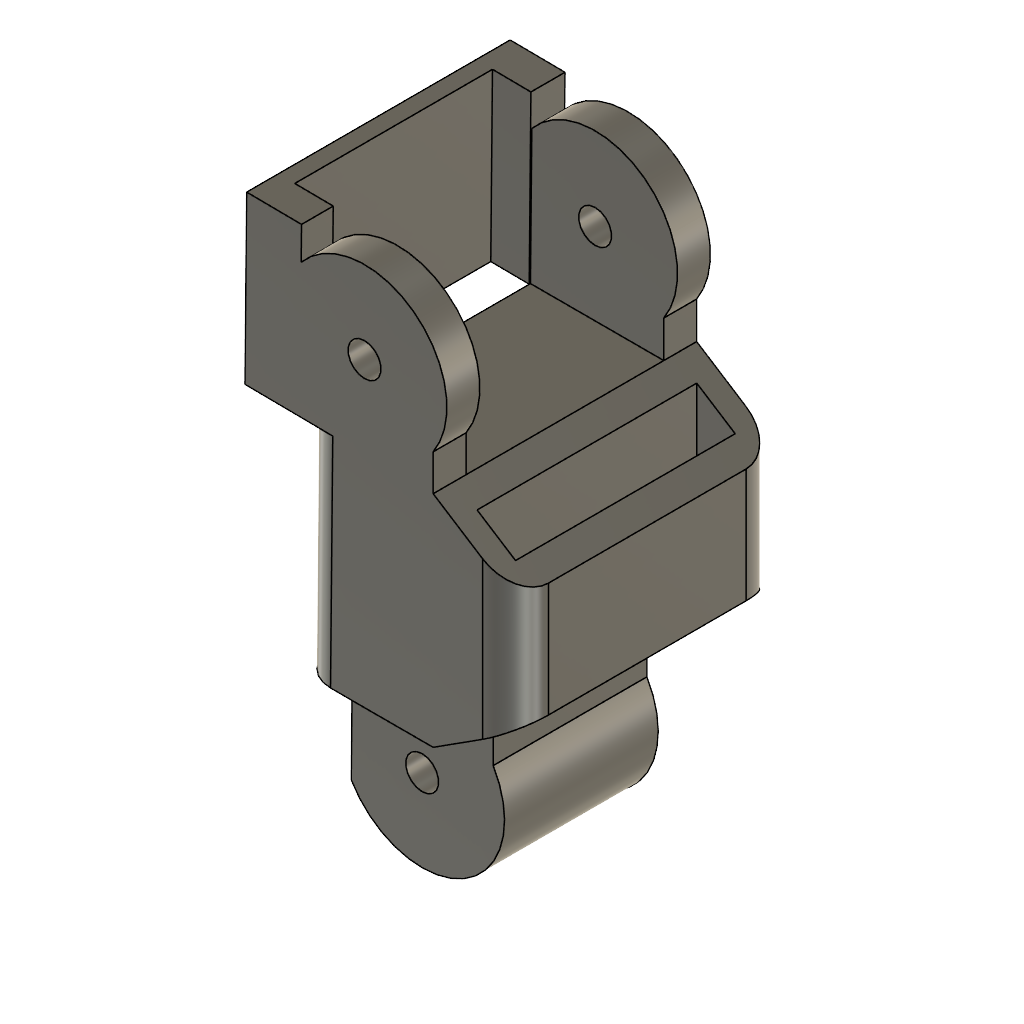
Fixed Hand Assembly V2 (Autodesk Fusion 360 archive; units mm, degrees)
design "Thumb END"
part number: 2026-11-07-22-03-41-443
Autodesk Fusion 360 part; units mm, degrees
sketch "Sketch1" plane through (0, 0, 0) normal (0, 1, 0) x (1, 0, 0)
  line L0 (0, 0) -> (25, 0)
  line L1 (25, 0) -> (25, -20)
  line L2 (25, -20) -> (0, -20)
  line L3 (0, -20) -> (0, 0)
  line L4 (12.5, -20) -> (25, -12)
  line L5 (12.5, 0) -> (25, -8)
  dimension "d1" = 25
  dimension "d2" = 20
  dimension "d3" = 8
  dimension "d4" = 8
  constraint horizontal L0
  constraint vertical L1
  constraint horizontal L2
  constraint vertical L3
  constraint coincident L0.start L3.end
  constraint midpoint L2 L4.start
  constraint coincident L1 L4.end
  constraint midpoint L0 L5.start
  constraint coincident L1 L5.end
  measures "d1" distance of L0.start L0.end
  measures "d2" distance of L0.start L2.end
  measures "d3" distance of L1.end L4.end
  measures "d4" distance of L0.end L5.end
extrude "Extrude1" add sketch "Sketch1" along normal mid plane 24 contours L0 L1 L2 L3 L4 L5 makes body 1
sketch "Sketch2" plane through (0, 0, 0) normal (0, 1, 0) x (1, 0, 0)
  circle A0 centre (6.5, -27.5) radius 7.5
  line L0 (0.0314, -20) -> (12.9686, -20)
  line L1 (12.9686, -20) -> (12.9686, -23.7043)
  line L2 (12.9686, -23.7043) -> (0.0314, -23.7043)
  line L3 (0.0314, -23.7043) -> (0.0314, -20)
  point P0 (12.5, -20)
  dimension "d7" = 15
  dimension "d8" = 7.5
  dimension "d9" = 6
  constraint horizontal L0
  constraint vertical L1
  constraint horizontal L2
  constraint vertical L3
  constraint coincident A0 L1.end
  constraint coincident A0 L2.end
  measures "d7" diameter of A0
  measures "d8" vertical distance of A0.centre P0
  measures "d9" horizontal distance of A0.centre P0
extrude "Extrude2" add sketch "Sketch2" along normal mid plane 14 bodies 1
sketch "Sketch3" plane through (0, -12, 0) normal (0, -1, 0) x (1, 0, 0)
  line L0 (25, 12) -> (12.5, 20)
  line L1 (12.5, 20) -> (0, 20)
  line L2 (0, 20) -> (0, 0)
  line L3 (0, 0) -> (12.5, 0)
  line L4 (12.5, 0) -> (25, 8)
  line L5 (25, 8) -> (25, 12)
  circle A0 centre (6.25, -7.5) radius 7.5
  line L6 (0, 0) -> (12.4995, 0)
  line L7 (12.4995, 0) -> (12.4995, -4.343)
  line L8 (12.4995, -4.343) -> (0, -4.343)
  line L9 (0, -4.343) -> (0, 0)
  dimension "d12" = 15
  dimension "d13" = 7.5
  dimension "d14" = 6.25
  constraint horizontal L6
  constraint vertical L7
  constraint horizontal L8
  constraint vertical L9
  constraint coincident L2.end L3.start
  measures "d12" diameter of A0
  measures "d13" vertical distance of L3.end A0.centre
  measures "d14" horizontal distance of L3.end A0.centre
extrude "Extrude3" add sketch "Sketch3" against normal blind 3 contours L3 A0 L6 L7 | L3 A0 L6 L9 | A0 L7 L8 L9 | A0 L7 L8 L9 bodies 1
sketch "Sketch4" plane through (0, 12, 0) normal (0, 1, 0) x (-1, 0, 0)
  line L0 (-12.5, 20) -> (-25, 12)
  line L1 (-25, 12) -> (-25, 8)
  line L2 (-25, 8) -> (-12.5, 0)
  line L3 (-12.5, 0) -> (0, 0)
  line L4 (0, 0) -> (0, 20)
  line L5 (0, 20) -> (-12.5, 20)
  circle A0 centre (-6.25, -7.45) radius 7.5
  line L6 (-12.5, 0) -> (-0.0053, 0)
  line L7 (-0.0053, 0) -> (-0.0053, -3.8158)
  line L8 (-0.0053, -3.8158) -> (-12.5, -3.8158)
  line L9 (-12.5, -3.8158) -> (-12.5, 0)
  dimension "d17" = 15
  dimension "d18" = 7.45
  dimension "d19" = 6.25
  constraint horizontal L6
  constraint vertical L7
  constraint horizontal L8
  constraint vertical L9
  constraint coincident L2.end L3.start
  measures "d17" diameter of A0
  measures "d18" vertical distance of L3.end A0.centre
  measures "d19" horizontal distance of L3.end A0.centre
extrude "Extrude4" add sketch "Sketch4" against normal blind 3 contours L3 A0 L6 L9 | L3 A0 L6 L7 | L3 A0 L6 L7 L8 L9 | A0 L7 L8 L9 bodies 1
hole "Hole1" at (6.5, 7, 27.5) direction (0, -1, 0) diameter 3 end through all bodies 1
hole "Hole2" at (6.25, 12, -7.45) direction (0, -1, 0) diameter 3 end through all bodies 1
move_body "Move1" bodies 1 to x (-1, 0, 0) y (0, 1, 0) z (0, 0, -1) at (-2.5, 0, 35)
move_body "Move2" bodies 1 to x (-1, 0, 0) y (0, -1, 0) z (0, 0, 1) at (-55, -24, 0)
sketch "Sketch5" plane through (0, -36, 0) normal (0, -1, 0) x (1, 0, 0)
  circle A0 centre (-46.25, 42.45) radius 1.5
  line L0 (-40, 15) -> (-27.5, 23)
  line L1 (-27.5, 23) -> (-27.5, 27)
  line L2 (-27.5, 27) -> (-40, 35)
  line L3 (-40, 35) -> (-40, 38.3042)
  arc A1 (-40, 38.3042) -> (-52.4947, 38.2962) centre (-46.25, 42.45) ccw
  line L4 (-52.4947, 38.2962) -> (-52.4947, 35)
  line L5 (-52.4947, 35) -> (-52.5, 35)
  line L6 (-52.5, 35) -> (-52.5, 15)
  line L7 (-52.5, 15) -> (-40, 15)
  line L8 (-52, 49) -> (-52.4947, 0.4697)
  line L9 (-52.4947, 0.4697) -> (-54.3255, 0.4883)
  line L10 (-54.3255, 0.4883) -> (-54.3255, 49)
  line L11 (-54.3255, 49) -> (-52, 49)
  constraint perpendicular L8 L9
  constraint vertical L10
  constraint horizontal L11
extrude "Extrude5" cut sketch "Sketch5" against normal blind 39 contours A1 L4 L5 L6 L7 L8 L9 L10 L11 | A1 L4 L5 L6 L7 L8 bodies 1
sketch "Sketch6" plane through (-52.494, 0, 0.5351) normal (-0.999948, 0, 0.010193) x (0, -1, 0)
  line L0 (31, 14.4657) -> (36, 14.4657)
  line L1 (36, 14.4657) -> (36, 46.7112)
  line L2 (36, 46.7112) -> (33, 46.7112)
  line L3 (33, 46.7112) -> (33, 34.4667)
  line L4 (33, 34.4667) -> (15, 34.4667)
  line L5 (15, 34.4667) -> (15, 46.7618)
  line L6 (15, 46.7618) -> (12, 46.7618)
  line L7 (12, 46.7618) -> (12, 14.4657)
  line L8 (12, 14.4657) -> (17, 14.4657)
  line L9 (17, 14.4657) -> (17, 3.1579)
  line L10 (17, 3.1579) -> (31, 3.1579)
  line L11 (31, 3.1579) -> (31, 14.4657)
  line L12 (12, 34.4667) -> (36, 34.4667)
  line L13 (36, 34.4667) -> (36, 46.7112)
  line L14 (36, 46.7112) -> (12, 46.7112)
  line L15 (12, 46.7112) -> (12, 34.4667)
  constraint horizontal L12
  constraint vertical L13
  constraint horizontal L14
  constraint vertical L15
  constraint coincident L1.end L2.start
  constraint coincident L7 L12.start
extrude "Extrude6" add sketch "Sketch6" along normal blind 5 separate body contours L1 L2 L3 L12 L13 L14 | L3 L4 L5 L12 L14 | L5 L7 L12 L14 L15 makes body 2
sketch "Sketch7" plane through (0.4761, 0, 46.7088) normal (0.010193, 0, 0.999948) x (0, 1, 0)
  line L0 (-36, 52.4967) -> (-12, 52.4967)
  line L1 (-12, 52.4967) -> (-12, 57.4967)
  line L2 (-12, 57.4967) -> (-36, 57.4967)
  line L3 (-36, 57.4967) -> (-36, 52.4967)
  line L4 (-15.1122, 52.4967) -> (-33.1122, 52.4967)
  line L5 (-33.1122, 52.4967) -> (-33.1122, 55.9967)
  line L6 (-33.1122, 55.9967) -> (-15.1122, 55.9967)
  line L7 (-15.1122, 55.9967) -> (-15.1122, 52.4967)
  dimension "d30" = 18
  dimension "d31" = 3.5
  constraint horizontal L4
  constraint vertical L5
  constraint horizontal L6
  constraint vertical L7
  constraint coincident L0 L4.start
  measures "d30" distance of L4.start L4.end
  measures "d31" distance of L4.start L6.end
extrude "Extrude7" cut sketch "Sketch7" against normal blind 16 contours L0 L4 L5 L6 L7 bodies 2
extrude "Extrude8" add 1 faces at (-54.8511, -13.0374, 47.2728) along direction (0.010193, 0, 0.999948) blind 3 on bodies 2 bodies 1 2
sketch "Sketch8" plane through (0, -36, 0) normal (0, -1, 0) x (1, 0, 0)
  line L0 (-52.1427, 35) -> (-52.3466, 15)
  line L1 (-52.3466, 15) -> (-40, 15)
  line L2 (-40, 15) -> (-27.5, 23)
  line L3 (-27.5, 23) -> (-27.5, 27)
  line L4 (-27.5, 27) -> (-40, 35)
  line L5 (-40, 35) -> (-40, 38.3042)
  arc A0 (-40, 38.3042) -> (-52.0179, 47.2439) centre (-46.25, 42.45) ccw
  line L6 (-52.0179, 47.2439) -> (-51.9873, 50.2437)
  line L7 (-51.9873, 50.2437) -> (-56.9871, 50.2947)
  line L8 (-56.9871, 50.2947) -> (-57.1424, 35.051)
  line L9 (-57.1424, 35.051) -> (-52.1427, 35)
  circle A1 centre (-46.25, 42.45) radius 1.5
  line L10 (-32.5, 30.2) -> (-27.5, 30.2)
  line L11 (-27.5, 30.2) -> (-27.5, 19.2)
  line L12 (-27.5, 19.2) -> (-32.5, 19.2)
  line L13 (-32.5, 19.2) -> (-32.5, 30.2)
  dimension "d36" = 5
  dimension "d37" = 11
  dimension "d38" = 5
  constraint horizontal L10
  constraint vertical L11
  constraint horizontal L12
  constraint vertical L13
  constraint coincident L4 L10.start
  measures "d36" distance of L10.start L10.end
  measures "d37" distance of L10.start L12.end
  measures "d38" distance of L3.end L13
extrude "Extrude9" cut sketch "Sketch8" against normal blind 29 contours L2 L3 L4 L11 L13 | L2 L11 L12 L13 | L4 L10 L11 bodies 1
sketch "Sketch9" plane through (0, 0, 35) normal (0, 0, 1) x (-1, 0, 0)
  line L0 (52.1427, 15) -> (52.1427, 15.1122)
  line L1 (52.1427, 15.1122) -> (52.1427, 33)
  line L2 (52.1427, 33) -> (40, 33)
  line L3 (40, 33) -> (40, 12)
  line L4 (40, 12) -> (40.0005, 12)
  line L5 (40.0005, 12) -> (40.0005, 15)
  line L6 (40.0005, 15) -> (52.1427, 15)
  line L7 (32.5, 12) -> (40, 12)
  line L8 (40, 12) -> (40, 36)
  line L9 (40, 36) -> (32.5, 36)
  line L10 (32.5, 36) -> (32.5, 12)
  line L11 (38, 14) -> (38, 34)
  line L12 (38, 34) -> (34.5, 34)
  line L13 (34.5, 34) -> (34.5, 14)
  line L14 (34.5, 14) -> (38, 14)
  dimension "d41" = -2
  constraint horizontal L7
  constraint vertical L8
  constraint horizontal L9
  constraint vertical L10
extrude "Extrude10" cut sketch "Sketch9" against normal blind 20.5 contours L11 L12 L13 L14 bodies 1
fillet "Fillet1" radius 3 4 edges at (-52.2446, -36, 25) (-32.5, -36, 25) (-32.5, -12, 25) (-52.2446, -12, 25) on bodies 1

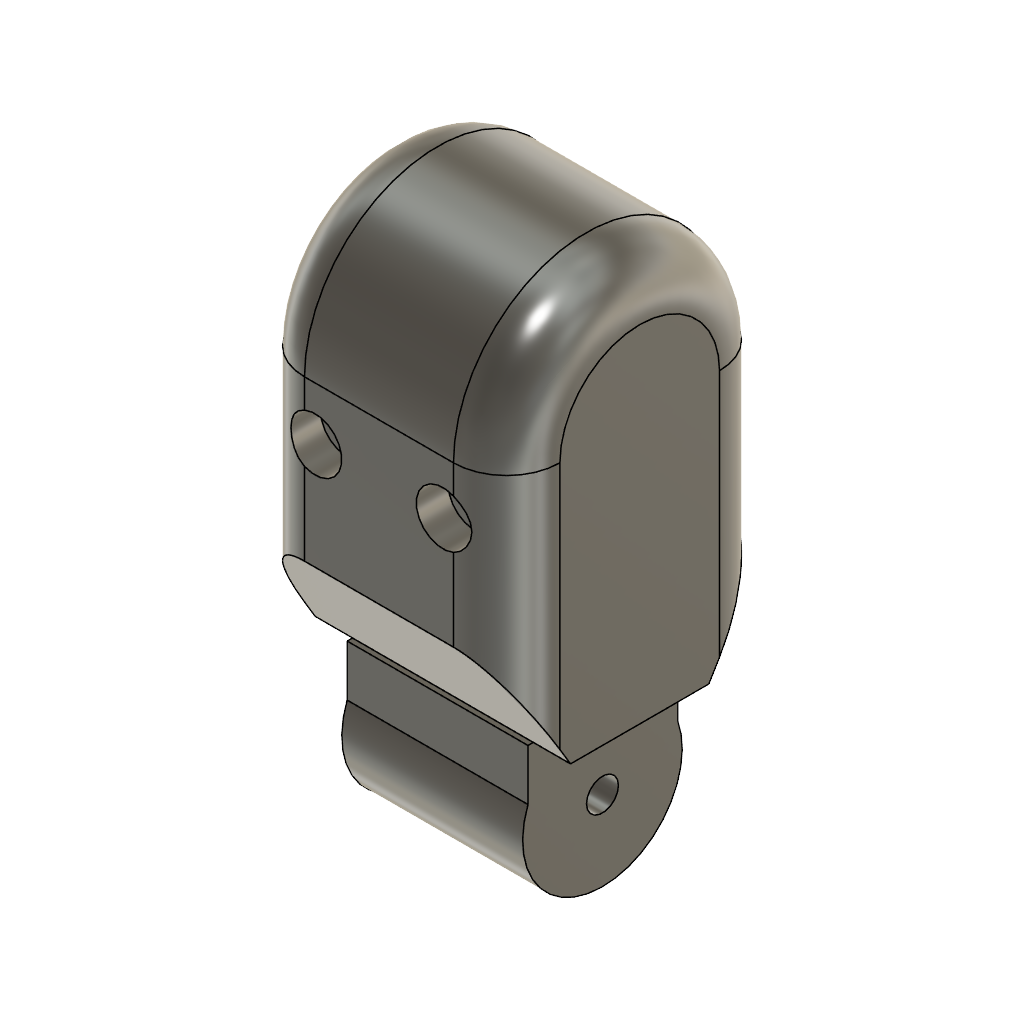
design "Thumb DISTAL"
part number: 2026-11-07-21-49-28-022
Autodesk Fusion 360 part; units mm, degrees
sketch "Sketch1" plane through (0, 0, 0) normal (1, 0, 0) x (0, 1, 0)
  line L0 (0, 0) -> (25, 0)
  line L1 (25, 0) -> (25, 25)
  line L2 (25, 25) -> (0, 25)
  line L3 (0, 25) -> (0, 0)
  circle A0 centre (12.5, 25) radius 12.5
  dimension "d1" = 25
  dimension "d2" = 25
  constraint horizontal L0
  constraint vertical L1
  constraint horizontal L2
  constraint vertical L3
  constraint coincident L0.start L3.end
  constraint midpoint L2 A0.centre
  constraint coincident L1.end A0
  measures "d1" distance of L0.start L0.end
  measures "d2" distance of L0.start L2.end
extrude "Extrude1" add sketch "Sketch1" along normal mid plane 24
sketch "Sketch2" plane through (0, 0, 0) normal (1, 0, 0) x (0, 1, 0)
  circle A0 centre (12.5, -7.5) radius 7.5
  line L0 (5.5, 0) -> (19.5814, 0)
  line L1 (19.5814, 0) -> (19.5814, -5.0295)
  line L2 (19.5814, -5.0295) -> (5.5, -5.0295)
  line L3 (5.5, -5.0295) -> (5.5, 0)
  point P0 (25, 0)
  dimension "d5" = 15
  dimension "d6" = 7.5
  dimension "d7" = 12.5
  constraint horizontal L0
  constraint vertical L1
  constraint horizontal L2
  constraint vertical L3
  constraint coincident A0 L1.end
  measures "d5" diameter of A0
  measures "d6" vertical distance of A0.centre P0
  measures "d7" horizontal distance of A0.centre P0
extrude "Extrude2" add sketch "Sketch2" along normal mid plane 17
hole "Hole1" at (8.5, 12.5, -7.5) direction (-1, 0, 0) diameter 3 depth 20 tip angle 180
sketch "Sketch3" plane through (0, 0, 0) normal (0, -1, 0) x (1, 0, 0)
  line L0 (-12, 0) -> (12, 0)
  line L1 (12, 0) -> (12, 25)
  line L2 (12, 25) -> (-12, 25)
  line L3 (-12, 25) -> (-12, 0)
  circle A0 centre (-6, 20) radius 2.5
  circle A1 centre (6, 20) radius 2.5
  dimension "d13" = 5
  dimension "d14" = 5
  dimension "d15" = 6
  dimension "d16" = 6
  dimension "d17" = 20
  dimension "d18" = 20
  measures "d13" diameter of A0
  measures "d14" diameter of A1
  measures "d15" horizontal distance of origin A1.centre
  measures "d16" horizontal distance of origin A0.centre
  measures "d17" vertical distance of L0.start A0.centre
  measures "d18" vertical distance of L0.end A1.centre
extrude "Extrude3" cut sketch "Sketch3" against normal blind 3 contours A0 | A1
sketch "Sketch4" plane through (12, 0, 0) normal (1, 0, 0) x (0, 1, 0)
  arc A0 (25, 25) -> (0, 25) centre (12.5, 25) ccw
  line L0 (0, 25) -> (0, 0)
  line L1 (0, 0) -> (25, 0)
  line L2 (25, 0) -> (25, 25)
  line L3 (0, 10) -> (6, 0)
  line L4 (19, 0) -> (25, 0)
  line L5 (0, 10) -> (0, 0)
  line L6 (0, 0) -> (6, 0)
  line L7 (25, 10) -> (25, 0)
  line L8 (25, 10) -> (19, 0)
  dimension "d21" = 6
  dimension "d22" = 6
  dimension "d23" = 10
  dimension "d24" = 10
  constraint coincident L0 L3.start
  constraint coincident L1 L3.end
  constraint coincident L1 L4.start
  constraint coincident L2 L7.start
  constraint coincident L1.end L2.start
  constraint coincident L0.end L1.start
  measures "d21" distance of L4.start L1.end
  measures "d22" distance of L3.end L0.end
  measures "d23" distance of L3.start L0.end
  measures "d24" distance of L7.start L1.end
extrude "Extrude4" cut sketch "Sketch4" against normal blind 24 contours L1 L2 L4 L7 L8 | L0 L1 L3 L5 L6
fillet "Fillet1" radius 5 6 edges at (12, 25, 17.5) (12, 12.5, 37.5) (12, 0, 17.5) (-12, 0, 17.5) (-12, 12.5, 37.5) (-12, 25, 17.5)
equation "d7 = ( 25 / 2 ) * 1 mm"

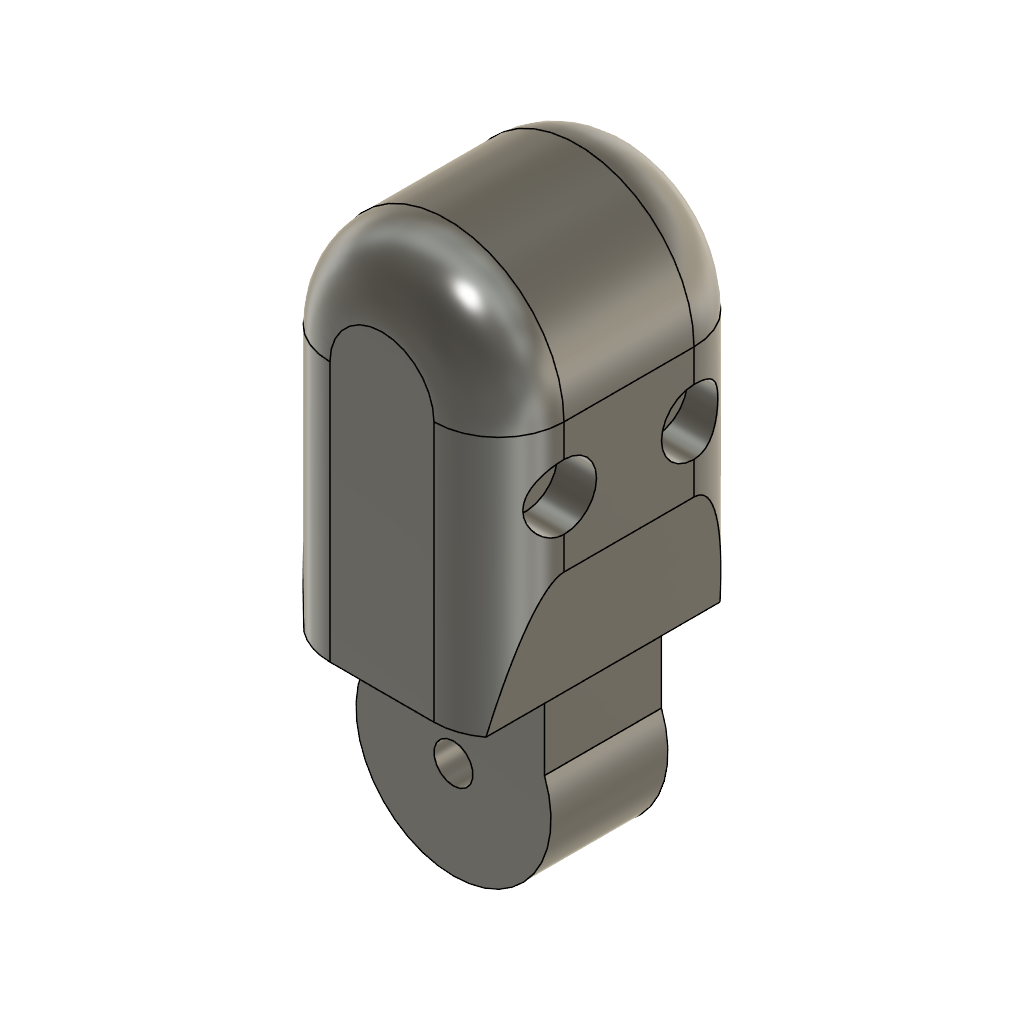
design "Pinkie finger DISTAL"
part number: 2026-11-08-09-32-45-711
Autodesk Fusion 360 part; units mm, degrees
sketch "Sketch1" plane through (0, 0, 0) normal (0, 1, 0) x (1, 0, 0)
  line L0 (0, 0) -> (18, 0)
  line L1 (18, 0) -> (18, -20)
  line L2 (18, -20) -> (0, -20)
  line L3 (0, -20) -> (0, 0)
  circle A0 centre (9, -20) radius 9
  dimension "d1" = 18
  dimension "d2" = 20
  dimension "d3" = 18
  constraint horizontal L0
  constraint vertical L1
  constraint horizontal L2
  constraint vertical L3
  constraint coincident L0.start L3.end
  constraint midpoint L2 A0.centre
  measures "d1" distance of L0.start L0.end
  measures "d2" distance of L0.start L2.end
  measures "d3" diameter of A0
extrude "Extrude1" add sketch "Sketch1" along normal mid plane 20
sketch "Sketch2" plane through (0, 0, 0) normal (0, 1, 0) x (1, 0, 0)
  circle A0 centre (9, 7.5) radius 7.5
  line L0 (2, 0) -> (16, 0)
  line L1 (16, 0) -> (16, 5.4)
  line L2 (16, 5.4) -> (2, 5.4)
  line L3 (2, 5.4) -> (2, 0)
  point P0 (18, 0)
  dimension "d6" = 15
  dimension "d7" = 7.5
  dimension "d8" = 9
  constraint horizontal L0
  constraint vertical L1
  constraint horizontal L2
  constraint vertical L3
  measures "d6" diameter of A0
  measures "d7" vertical distance of A0.centre P0
  measures "d8" horizontal distance of A0.centre P0
extrude "Extrude2" add sketch "Sketch2" along normal mid plane 9
hole "Hole1" at (9, -4.5, -7.5) direction (0, 1, 0) diameter 3 end through all
sketch "Sketch3" plane through (18, 0, 0) normal (1, 0, 0) x (0, 1, 0)
  line L0 (-10, 0) -> (10, 0)
  line L1 (10, 0) -> (10, 20)
  line L2 (10, 20) -> (-10, 20)
  line L3 (-10, 20) -> (-10, 0)
  circle A0 centre (-5, 15) radius 2.5
  circle A1 centre (5, 15) radius 2.5
  dimension "d13" = 5
  dimension "d14" = 5
  measures "d13" diameter of A0
  measures "d14" diameter of A1
extrude "Extrude3" cut sketch "Sketch3" against normal blind 3 contours A0 | A1
sketch "Sketch4" plane through (0, -10, 0) normal (0, -1, 0) x (1, 0, 0)
  arc A0 (18, 20) -> (0, 20) centre (9, 20) ccw
  line L0 (0, 20) -> (0, 0)
  line L1 (0, 0) -> (18, 0)
  line L2 (18, 0) -> (18, 20)
  line L3 (0, 10) -> (2, 0)
  line L4 (16, 0) -> (18, 10)
  line L5 (2, 0) -> (0, 0)
  line L6 (0, 10) -> (0, 0)
  line L7 (16, 0) -> (18, 0)
  line L8 (18, 10) -> (18, 0)
  dimension "d17" = 10
  dimension "d18" = 2
  dimension "d19" = 2
  dimension "d20" = 10
  constraint coincident L0 L3.start
  constraint coincident L1 L3.end
  constraint coincident L1 L4.start
  constraint coincident L2 L4.end
  constraint coincident L0.end L1.start
  constraint coincident L1.end L2.start
  measures "d17" distance of L4.end L1.end
  measures "d18" distance of L4.start L1.end
  measures "d19" distance of L3.end L0.end
  measures "d20" distance of L3.start L0.end
extrude "Extrude4" cut sketch "Sketch4" against normal blind 25 contours L1 L2 L4 L7 L8 | L0 L1 L3 L5 L6
fillet "Fillet1" radius 5 6 edges at (0, 10, 15) (9, 10, 29) (18, 10, 15) (18, -10, 15) (9, -10, 29) (0, -10, 15)
equation "d8 = ( 18 / 2 ) * 1 mm"

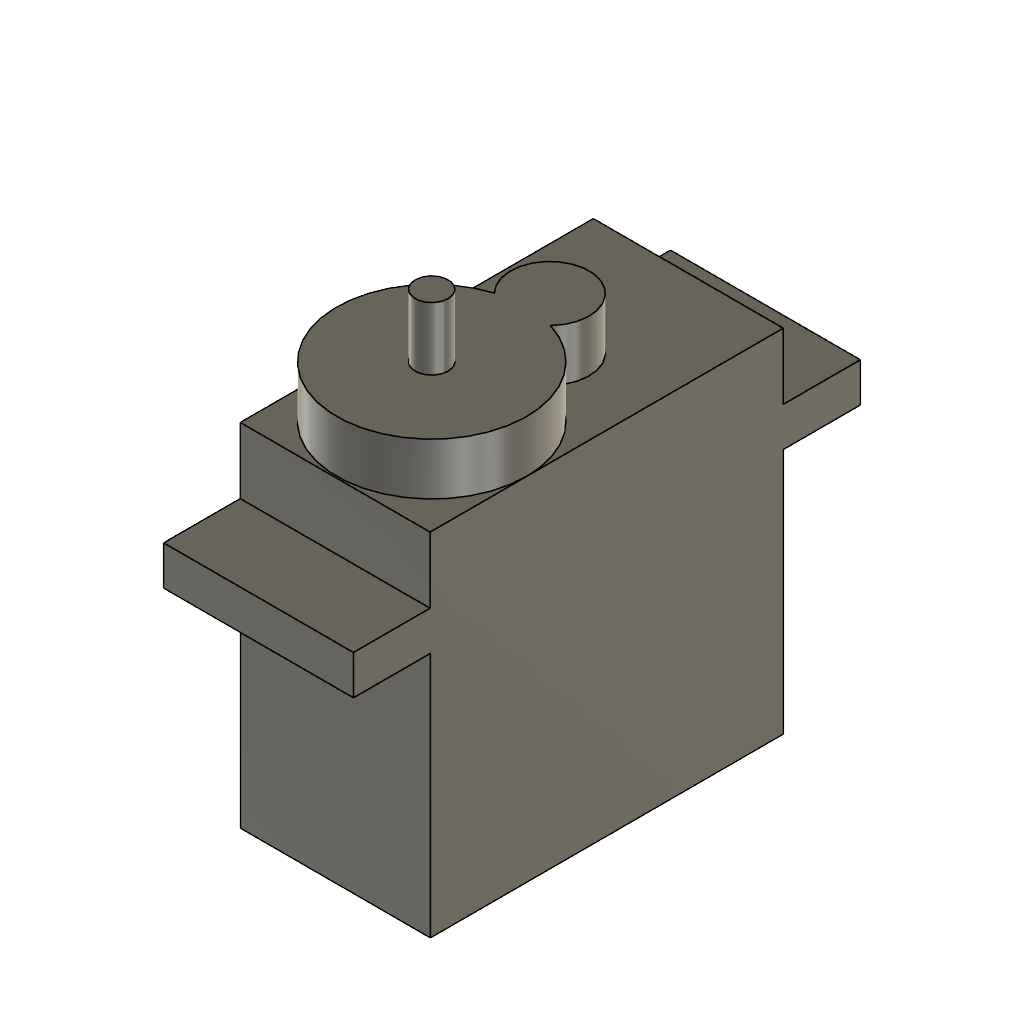
design "Servo"
part number: 2026-11-08-19-13-35-138
Autodesk Fusion 360 part; units mm, degrees
sketch "Sketch1" plane through (0, 0, 0) normal (1, 0, 0) x (0, 1, 0)
  line L0 (0, 0) -> (22.5, 0)
  line L1 (22.5, 0) -> (22.5, 15.7)
  line L2 (22.5, 15.7) -> (0, 15.7)
  line L3 (0, 15.7) -> (0, 0)
  line L4 (0, 15.7) -> (-4.9, 15.7)
  line L5 (-4.9, 15.7) -> (-4.9, 18.2)
  line L6 (-4.9, 18.2) -> (27.4, 18.2)
  line L7 (27.4, 18.2) -> (27.4, 15.7)
  line L8 (27.4, 15.7) -> (22.5, 15.7)
  line L9 (-0.0178, 18.2) -> (-0.0178, 22.4)
  line L10 (-0.0178, 22.4) -> (22.4822, 22.4)
  line L11 (22.4822, 22.4) -> (22.4822, 18.2)
  dimension "d1" = 22.5
  dimension "d2" = 15.7
  dimension "d3" = 18.2
  dimension "d4" = 32.3
  dimension "d5" = 22.4
  dimension "d6" = 22.5
  constraint horizontal L0
  constraint vertical L1
  constraint horizontal L2
  constraint vertical L3
  constraint coincident L0.start L3.end
  constraint perpendicular L3 L4
  constraint perpendicular L2 L5
  constraint perpendicular L3 L6
  constraint perpendicular L2 L7
  constraint perpendicular L1 L8
  constraint coincident L6 L9.start
  constraint perpendicular L6 L9
  constraint perpendicular L9 L10
  constraint coincident L6 L11.end
  constraint perpendicular L6 L11
  constraint equal L4 L8
  measures "d1" distance of L0.start L0.end
  measures "d2" distance of L0.start L2.end
  measures "d3" vertical distance of L0.start L5.end
  measures "d4" distance of L5.end L6.end
  measures "d5" vertical distance of L0.start L9.end
  measures "d6" distance of L9.end L10.end
extrude "Extrude1" add sketch "Sketch1" along normal blind 12.1
sketch "Sketch2" plane through (0, 0, 22.4) normal (0, 0, 1) x (-1, 0, 0)
  line L0 (0, -22.4822) -> (0, 0.0178)
  line L1 (0, 0.0178) -> (-12.1, 0.0178)
  line L2 (-12.1, 0.0178) -> (-12.1, -22.4822)
  line L3 (-12.1, -22.4822) -> (0, -22.4822)
  line L4 (-6.05, 0.0178) -> (-6.05, -22.4822) construction
  circle A0 centre (-6.05, -6.1346) radius 6.05
  circle A1 centre (-6.05, -13.6621) radius 2.5
  dimension "d10" = 12.1
  dimension "d11" = 5
  constraint midpoint L1 L4.start
  constraint midpoint L3 L4.end
  constraint coincident L4 A0.centre
  constraint coincident L4 A1.centre
  measures "d10" diameter of A0
  measures "d11" diameter of A1
extrude "Extrude2" add sketch "Sketch2" along normal blind 3.3 contours A0 A1 | A0 A1 | A0 A1
sketch "Sketch3" plane through (0, 0, 25.7) normal (0, 0, 1) x (-1, 0, 0)
  arc A0 (-7.8376, -11.9145) -> (-4.2624, -11.9145) centre (-6.05, -13.6621) ccw
  arc A1 (-4.2624, -11.9145) -> (-7.8376, -11.9145) centre (-6.05, -6.1346) ccw
  circle A2 centre (-6.05, -6.1346) radius 2.43
  circle A3 centre (-6.05, -6.1346) radius 1.05
  dimension "d14" = 4.86
  dimension "d15" = 2.1
  constraint concentric A1 A2
  constraint concentric A1 A3
  measures "d14" diameter of A2
  measures "d15" diameter of A3
extrude "Extrude3" add sketch "Sketch3" along normal blind 4 contours A3

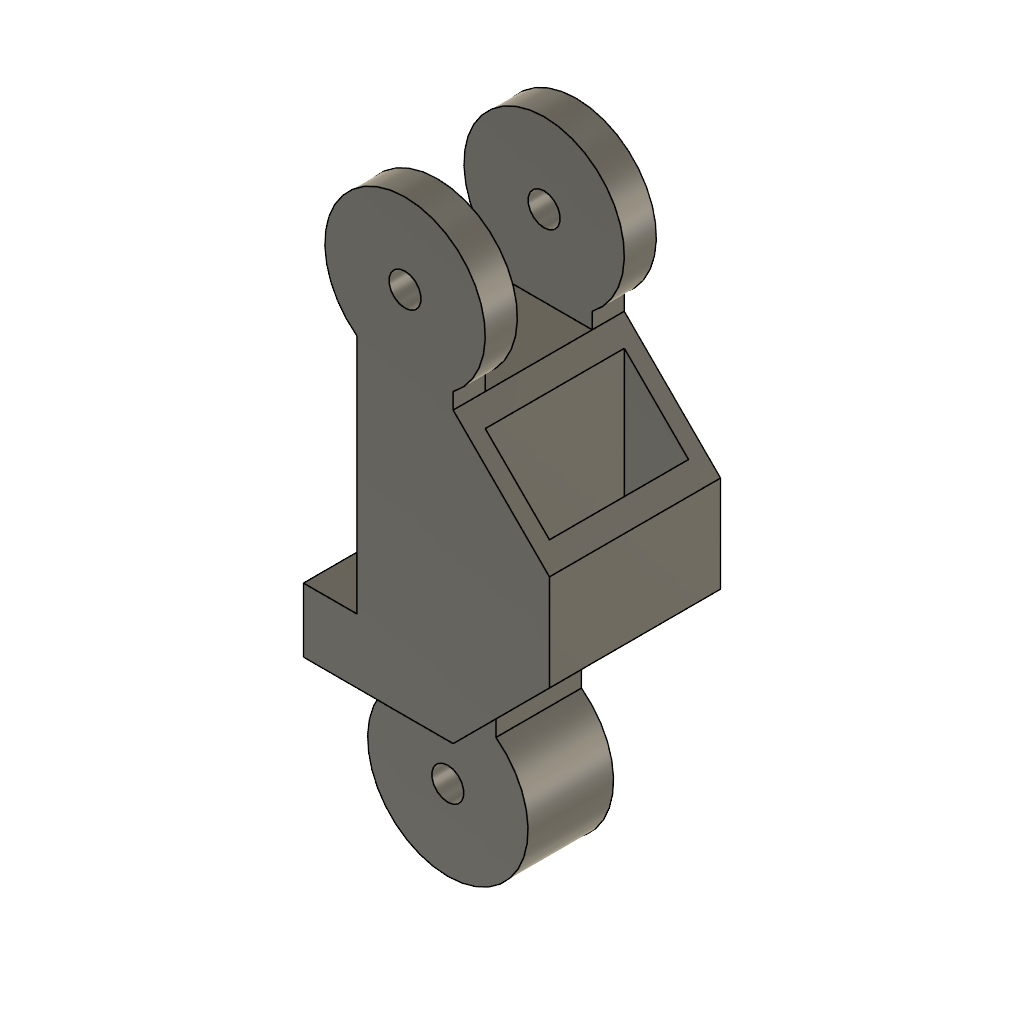
design "Pinkie Finger MIDDLE"
part number: 2026-11-08-09-24-04-675
Autodesk Fusion 360 part; units mm, degrees
sketch "Sketch1" plane through (0, 0, 0) normal (0, 1, 0) x (1, 0, 0)
  line L0 (0, 0) -> (18, 0)
  line L1 (18, 0) -> (18, -27)
  line L2 (18, -27) -> (0, -27)
  line L3 (0, -27) -> (0, 0)
  line L4 (9, -27) -> (18, -18)
  line L5 (9, 0) -> (18, -9)
  dimension "d1" = 18
  dimension "d2" = 27
  dimension "d3" = 9
  dimension "d4" = 9
  constraint horizontal L0
  constraint vertical L1
  constraint horizontal L2
  constraint vertical L3
  constraint coincident L0.start L3.end
  constraint midpoint L2 L4.start
  constraint coincident L1 L4.end
  constraint midpoint L0 L5.start
  constraint coincident L1 L5.end
  measures "d1" distance of L0.start L0.end
  measures "d2" distance of L0.start L2.end
  measures "d3" vertical distance of L4.start L4.end
  measures "d4" distance of L0.end L5.end
extrude "Extrude1" add sketch "Sketch1" along normal mid plane 16 contours L0 L1 L2 L3 L4 L5
sketch "Sketch2" plane through (0, 0, 0) normal (0, 1, 0) x (1, 0, 0)
  circle A0 centre (4.5, 7.5) radius 7.5
  line L0 (0, 0) -> (0, 1.5)
  line L1 (9, 0) -> (9, 1.5)
  line L2 (9, 0) -> (0, 0)
  dimension "d7" = 15
  dimension "d8" = 7.5
  dimension "d9" = 4.5
  constraint coincident L0.start L2.end
  constraint coincident A0 L0.end
  constraint vertical L0
  constraint coincident A0 L1.end
  constraint parallel L0 L1
  constraint perpendicular L0 L2
  measures "d7" diameter of A0
  measures "d8" vertical distance of L0.start A0.centre
  measures "d9" horizontal distance of L0.start A0.centre
extrude "Extrude2" add sketch "Sketch2" along normal mid plane 8
sketch "Sketch3" plane through (0, 8, 0) normal (0, 1, 0) x (-1, 0, 0)
  line L0 (-9, 27) -> (-18, 18)
  line L1 (-18, 18) -> (-18, 9)
  line L2 (-18, 9) -> (-9, 0)
  line L3 (-9, 0) -> (0, 0)
  line L4 (0, 0) -> (0, 27)
  line L5 (0, 27) -> (-9, 27)
  circle A0 centre (-4.5, 34.5) radius 7.5
  line L6 (-9, 27) -> (-9, 28.5)
  line L7 (0, 27) -> (0, 28.5)
  line L8 (-9, 27) -> (0, 27)
  dimension "d12" = 15
  dimension "d13" = 7.5
  dimension "d14" = 4.5
  constraint coincident L0.start L5.end
  constraint coincident A0 L6.end
  constraint perpendicular L5 L6
  constraint coincident L4.end L5.start
  constraint coincident A0 L7.end
  constraint perpendicular L5 L7
  measures "d12" diameter of A0
  measures "d13" vertical distance of L4.end A0.centre
  measures "d14" horizontal distance of L4.end A0.centre
extrude "Extrude3" add sketch "Sketch3" against normal blind 3 contours L5 A0 L6 L8 | L5 A0 L7 L8 | A0
sketch "Sketch4" plane through (0, -8, 0) normal (0, -1, 0) x (1, 0, 0)
  line L0 (18, 18) -> (9, 27)
  line L1 (9, 27) -> (0, 27)
  line L2 (0, 27) -> (0, 0)
  line L3 (0, 0) -> (9, 0)
  line L4 (9, 0) -> (18, 9)
  line L5 (18, 9) -> (18, 18)
  circle A0 centre (4.5, 34.5) radius 7.5
  line L6 (0, 27) -> (0, 28.5)
  line L7 (9, 27) -> (9, 28.5)
  line L8 (9, 27) -> (0, 27)
  dimension "d17" = 15
  dimension "d18" = 7.5
  dimension "d19" = 4.5
  constraint coincident L1.end L2.start
  constraint coincident A0 L6.end
  constraint perpendicular L1 L6
  constraint coincident L0.end L1.start
  constraint coincident A0 L7.end
  constraint perpendicular L1 L7
  measures "d17" diameter of A0
  measures "d18" vertical distance of L0.end A0.centre
  measures "d19" horizontal distance of L0.end A0.centre
extrude "Extrude4" add sketch "Sketch4" against normal blind 3 contours L1 A0 L7 L8 | L1 A0 L6 L8 | A0
hole "Hole1" at (4.5, -8, 34.5) direction (0, 1, 0) diameter 3 end through all
hole "Hole2" at (4.5, -4, -7.5) direction (0, 1, 0) diameter 3 end through all
sketch "Sketch5" plane through (0, 0, 27) normal (0, 0, 1) x (-1, 0, 0)
  line L0 (0, 5) -> (-9, 5)
  line L1 (-9, 5) -> (-9, -5)
  line L2 (-9, -5) -> (0, -5)
  line L3 (0, -5) -> (0, 5)
  line L4 (-18, -8) -> (-9, -8)
  line L5 (-9, -8) -> (-9, 8)
  line L6 (-9, 8) -> (-18, 8)
  line L7 (-18, 8) -> (-18, -8)
  line L8 (-10.5, -6.5) -> (-10.5, 6.5)
  line L9 (-10.5, 6.5) -> (-16.5, 6.5)
  line L10 (-16.5, 6.5) -> (-16.5, -6.5)
  line L11 (-16.5, -6.5) -> (-10.5, -6.5)
  dimension "d26" = -1.5
  constraint horizontal L4
  constraint vertical L5
  constraint horizontal L6
  constraint vertical L7
extrude "Extrude5" cut sketch "Sketch5" against normal blind 29 contours L8 L9 L10 L11
sketch "Sketch6" plane through (0, 0, 0) normal (-1, 0, 0) x (0, -1, 0)
  line L0 (5, 27) -> (-5, 27)
  line L1 (-5, 27) -> (-5, 28.5)
  line L2 (-5, 28.5) -> (-8, 28.5)
  line L3 (-8, 28.5) -> (-8, 0)
  line L4 (-8, 0) -> (-4, 0)
  line L5 (-4, 0) -> (-4, -1.5)
  line L6 (-4, -1.5) -> (4, -1.5)
  line L7 (4, -1.5) -> (4, 0)
  line L8 (4, 0) -> (8, 0)
  line L9 (8, 0) -> (8, 28.5)
  line L10 (8, 28.5) -> (5, 28.5)
  line L11 (5, 28.5) -> (5, 27)
  line L12 (-8, 0) -> (8, 0)
  line L13 (8, 0) -> (8, 6)
  line L14 (8, 6) -> (-8, 6)
  line L15 (-8, 6) -> (-8, 0)
  constraint horizontal L12
  constraint vertical L13
  constraint horizontal L14
  constraint vertical L15
  constraint coincident L9 L13.end
  constraint coincident L3.end L4.start
extrude "Extrude6" add sketch "Sketch6" along normal blind 5 contours L3 L4 L8 L9 L12 L13 L14 L15
equation "d3 = ( 27 / 3 ) * 1 mm"
equation "d4 = ( 27 / 3 ) * 1 mm"
equation "d9 = ( 9 / 2 ) * 1 mm"

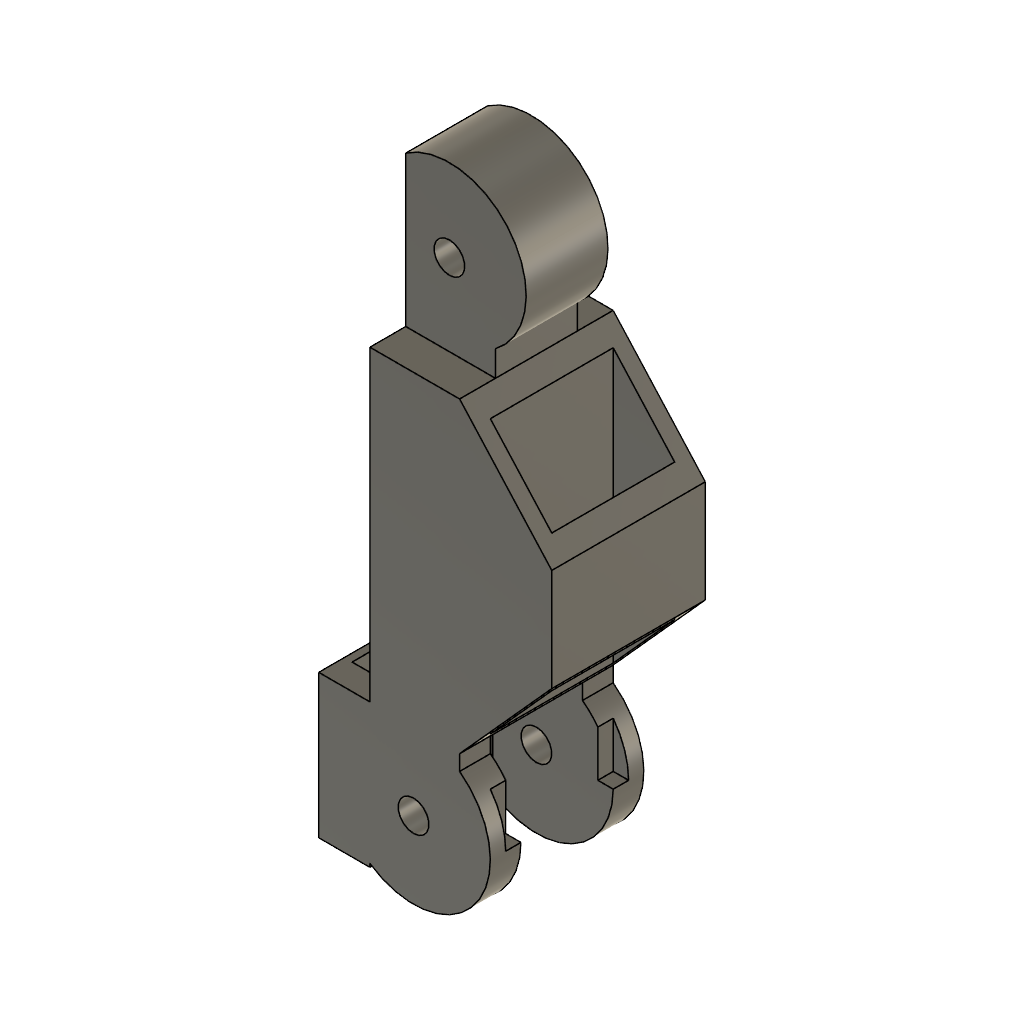
design "Pinkie Finger END"
part number: 2026-11-08-09-14-35-808
Autodesk Fusion 360 part; units mm, degrees
sketch "Sketch1" plane through (0, 0, 0) normal (0, 1, 0) x (1, 0, 0)
  line L0 (0, 0) -> (18, 0)
  line L1 (18, 0) -> (18, -30)
  line L2 (18, -30) -> (0, -30)
  line L3 (0, -30) -> (0, 0)
  line L4 (9, -30) -> (18, -20)
  line L5 (9, 0) -> (18, -10)
  dimension "d1" = 18
  dimension "d2" = 30
  dimension "d3" = 10
  dimension "d4" = 10
  constraint horizontal L0
  constraint vertical L1
  constraint horizontal L2
  constraint vertical L3
  constraint coincident L0.start L3.end
  constraint midpoint L2 L4.start
  constraint coincident L1 L4.end
  constraint midpoint L0 L5.start
  constraint coincident L1 L5.end
  measures "d1" distance of L0.start L0.end
  measures "d2" distance of L0.start L2.end
  measures "d3" distance of L1.end L4.end
  measures "d4" distance of L0.end L5.end
extrude "Extrude1" add sketch "Sketch1" along normal mid plane 15 contours L0 L1 L2 L3 L4 L5 makes body 1
sketch "Sketch2" plane through (0, 0, 0) normal (0, 1, 0) x (1, 0, 0)
  circle A0 centre (4.5, -38.5) radius 7.5
  line L0 (0, -30) -> (0, -32.5)
  line L1 (9, -30) -> (9, -32.5)
  line L2 (9, -30) -> (0, -30)
  point P0 (9, -30)
  point P1 (0, -30)
  dimension "d7" = 15
  dimension "d8" = 8.5
  dimension "d9" = 4.5
  constraint coincident P1 L0.start
  constraint coincident A0 L0.end
  constraint vertical L0
  constraint coincident P0 L1.start
  constraint coincident A0 L1.end
  constraint parallel L0 L1
  measures "d7" diameter of A0
  measures "d8" vertical distance of A0.centre P0
  measures "d9" horizontal distance of A0.centre L0.start
extrude "Extrude2" add sketch "Sketch2" along normal mid plane 8 bodies 1
sketch "Sketch3" plane through (0, -7.5, 0) normal (0, -1, 0) x (1, 0, 0)
  line L0 (18, 20) -> (9, 30)
  line L1 (9, 30) -> (0, 30)
  line L2 (0, 30) -> (0, 0)
  line L3 (0, 0) -> (9, 0)
  line L4 (9, 0) -> (18, 10)
  line L5 (18, 10) -> (18, 20)
  circle A0 centre (4.5, -7.5) radius 7.5
  line L6 (0, 0) -> (0, -1.5)
  line L7 (9, 0) -> (9, -1.5)
  line L8 (9, 0) -> (0, 0)
  dimension "d12" = 15
  dimension "d13" = 7.5
  dimension "d14" = 4.5
  constraint coincident L2.end L3.start
  constraint coincident A0 L6.end
  constraint perpendicular L3 L6
  constraint coincident L3.end L4.start
  constraint coincident A0 L7.end
  constraint perpendicular L3 L7
  measures "d12" diameter of A0
  measures "d13" vertical distance of L3.end A0.centre
  measures "d14" horizontal distance of L2.end A0.centre
extrude "Extrude3" add sketch "Sketch3" against normal blind 3 contours L3 A0 L7 L8 | L3 A0 L6 L8 | A0 bodies 1
sketch "Sketch4" plane through (0, 7.5, 0) normal (0, 1, 0) x (-1, 0, 0)
  line L0 (-9, 30) -> (-18, 20)
  line L1 (-18, 20) -> (-18, 10)
  line L2 (-18, 10) -> (-9, 0)
  line L3 (-9, 0) -> (0, 0)
  line L4 (0, 0) -> (0, 30)
  line L5 (0, 30) -> (-9, 30)
  circle A0 centre (-4.5, -7.5) radius 7.5
  line L6 (-9, 0) -> (-9, -1.5)
  line L7 (0, 0) -> (0, -1.5)
  line L8 (0, 0) -> (-9, 0)
  dimension "d17" = 15
  dimension "d18" = 7.5
  dimension "d19" = 4.5
  constraint coincident L2.end L3.start
  constraint coincident A0 L6.end
  constraint perpendicular L3 L6
  constraint coincident L3.end L4.start
  constraint coincident A0 L7.end
  constraint perpendicular L3 L7
  measures "d17" diameter of A0
  measures "d18" vertical distance of L3.end A0.centre
  measures "d19" horizontal distance of L2.end A0.centre
extrude "Extrude4" add sketch "Sketch4" against normal blind 3 contours L3 A0 L7 L8 | L3 A0 L6 L8 | A0 bodies 1
hole "Hole1" at (4.5, 4, 37.9612) direction (0, -1, 0) diameter 3 end through all bodies 1
hole "Hole2" at (4.5, 7.5, -7.5) direction (0, -1, 0) diameter 3 end through all bodies 1
sketch "Sketch5" plane through (0, 0, 30) normal (0, 0, 1) x (-1, 0, 0)
  line L0 (-9, 4) -> (0, 4)
  line L1 (0, 4) -> (0, 7.5)
  line L2 (0, 7.5) -> (-9, 7.5)
  line L3 (-9, 7.5) -> (-9, 4)
  line L4 (-9, 7.5) -> (-18, 7.5)
  line L5 (-18, 7.5) -> (-18, -7.5)
  line L6 (-18, -7.5) -> (-9, -7.5)
  line L7 (-9, -7.5) -> (-9, 7.5)
  line L8 (-10.5, 6) -> (-16.5, 6)
  line L9 (-16.5, 6) -> (-16.5, -6)
  line L10 (-16.5, -6) -> (-10.5, -6)
  line L11 (-10.5, -6) -> (-10.5, 6)
  dimension "d26" = -1.5
  constraint horizontal L4
  constraint vertical L5
  constraint horizontal L6
  constraint vertical L7
  constraint coincident L2.end L3.start
extrude "Extrude5" cut sketch "Sketch5" against normal blind 37.5 contours L8 L9 L10 L11 bodies 1
sketch "Sketch6" plane through (0, -7.5, 0) normal (0, -1, 0) x (1, 0, 0)
  circle A0 centre (4.5, -7.5) radius 1.5
  line L0 (18, 20) -> (9, 30)
  line L1 (9, 30) -> (0, 30)
  line L2 (0, 30) -> (0, -1.5)
  arc A1 (0, -1.5) -> (9, -1.5) centre (4.5, -7.5) ccw
  line L3 (9, -1.5) -> (9, 0)
  line L4 (9, 0) -> (18, 10)
  line L5 (18, 10) -> (18, 20)
  line L6 (0.2309, 45.3336) -> (0.2309, -13.6664)
  line L7 (0.2309, -13.6664) -> (-3.7691, -13.6664)
  line L8 (-3.7691, -13.6664) -> (-3.7691, 45.3336)
  line L9 (-3.7691, 45.3336) -> (0.2309, 45.3336)
  dimension "d29" = 4
  constraint coincident A1 L6.end
  constraint perpendicular L1 L6
  constraint perpendicular L2 L7
  constraint perpendicular L7 L8
  constraint perpendicular L6 L9
  measures "d29" distance of L6.end L7.end
extrude "Extrude6" cut sketch "Sketch6" against normal blind 35 contours L1 L2 A1 L6 | L1 L2 A1 L6 L7 L8 L9 bodies 1
sketch "Sketch7" plane through (0.2309, 0, 0) normal (-1, 0, 0) x (0, -1, 0)
  line L0 (-4.5, -13.6664) -> (-4.5, 0)
  line L1 (-4.5, 0) -> (4.5, 0)
  line L2 (4.5, 0) -> (4.5, -13.6664)
  line L3 (4.5, -13.6664) -> (7.5, -13.6664)
  line L4 (7.5, -13.6664) -> (7.5, 30)
  line L5 (7.5, 30) -> (4, 30)
  line L6 (4, 30) -> (4, 44.6664)
  line L7 (4, 44.6664) -> (-4, 44.6664)
  line L8 (-4, 44.6664) -> (-4, 30)
  line L9 (-4, 30) -> (-7.5, 30)
  line L10 (-7.5, 30) -> (-7.5, -13.6664)
  line L11 (-7.5, -13.6664) -> (-4.5, -13.6664)
  line L12 (-7.5, 0) -> (7.5, 0)
  line L13 (7.5, 0) -> (7.5, -12)
  line L14 (7.5, -12) -> (-7.5, -12)
  line L15 (-7.5, -12) -> (-7.5, 0)
  dimension "d32" = 12
  constraint horizontal L12
  constraint vertical L13
  constraint horizontal L14
  constraint vertical L15
  constraint coincident L10 L12.start
  measures "d32" distance of L12.start L14.end
extrude "Extrude7" add sketch "Sketch7" along normal blind 5 separate body contours L0 L10 L12 L14 L15 | L0 L1 L2 L12 L14 | L2 L4 L12 L13 L14 makes body 2
sketch "Sketch8" plane through (0, 0, -12) normal (0, 0, -1) x (1, 0, 0)
  line L0 (0.2309, -7.5) -> (0.2309, 7.5)
  line L1 (0.2309, 7.5) -> (-4.7691, 7.5)
  line L2 (-4.7691, 7.5) -> (-4.7691, -7.5)
  line L3 (-4.7691, -7.5) -> (0.2309, -7.5)
  line L4 (0.2309, -4.4716) -> (-4, -4.4716)
  line L5 (-4, -4.4716) -> (-4, 5)
  line L6 (-4, 5) -> (0.2309, 5)
  line L7 (0.2309, 5) -> (0.2309, -4.4716)
  constraint horizontal L4
  constraint vertical L5
  constraint horizontal L6
  constraint vertical L7
  constraint coincident L0 L4.start
extrude "Extrude8" cut sketch "Sketch8" against normal blind 22 contours L0 L4 L5 L6 L7 bodies 2
extrude "Extrude9" add 1 faces at (-2.846, 6.4905, -12) along direction (0, 0, -1) blind 2 on bodies 2 bodies 1 2
equation "d9 = ( 9 / 2 ) * 1 mm"
equation "d14 = ( 9 / 2 ) * 1 mm"

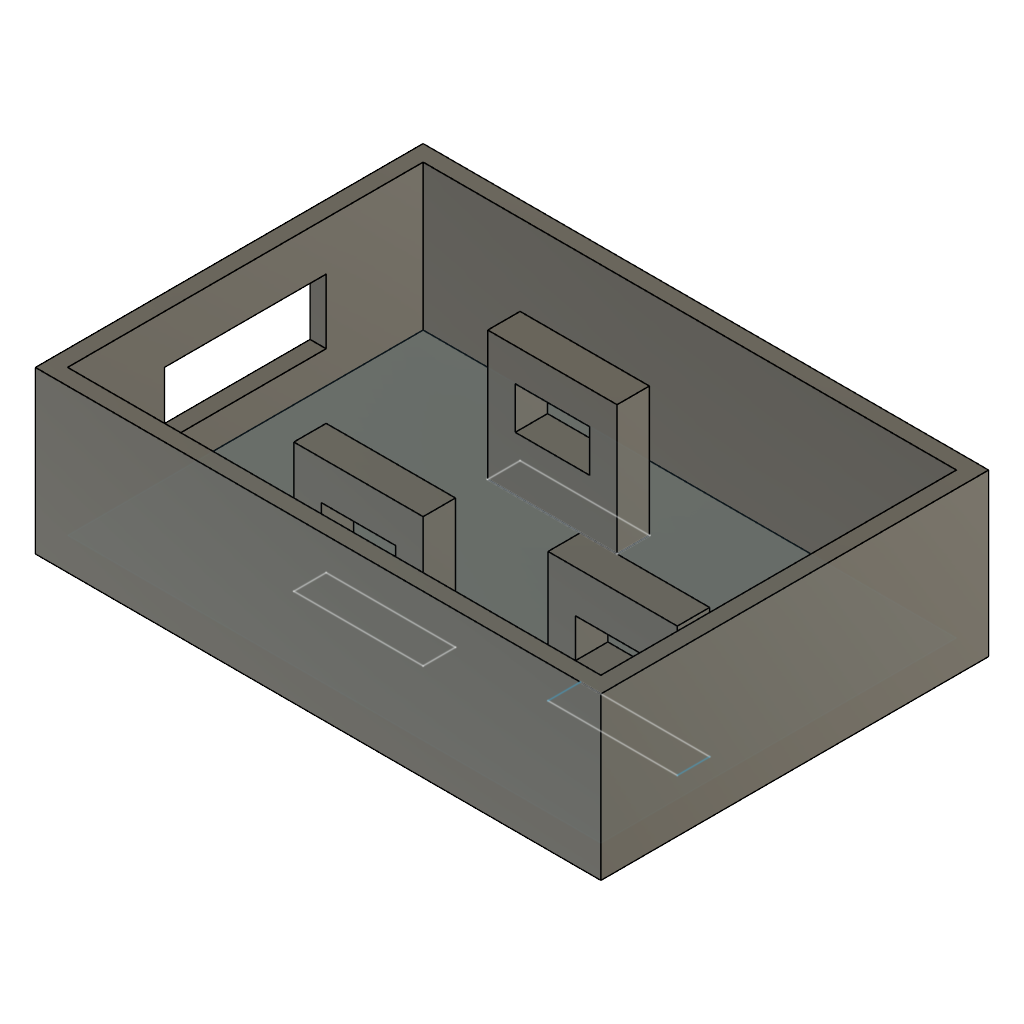
design "Servo Box"
part number: 2026-11-08-18-53-16-561
Autodesk Fusion 360 part; units mm, degrees
sketch "Sketch1" plane through (0, 0, 0) normal (0, 1, 0) x (1, 0, 0)
  line L0 (0, 0) -> (175, 0)
  line L1 (175, 0) -> (175, -120)
  line L2 (175, -120) -> (0, -120)
  line L3 (0, -120) -> (0, 0)
  dimension "d1" = 175
  dimension "d2" = 120
  constraint horizontal L0
  constraint vertical L1
  constraint horizontal L2
  constraint vertical L3
  constraint coincident L0.start L3.end
  measures "d1" distance of L0.start L0.end
  measures "d2" distance of L0.start L2.end
extrude "Extrude1" add sketch "Sketch1" along normal blind 50
shell "Shell1" thickness 5 removed faces 1 at (58.3333, 0, 80)
sketch "Sketch2" plane through (0, 0, 0) normal (-1, 0, 0) x (0, -1, 0)
  line L0 (0, 0) -> (0, 120)
  line L1 (0, 120) -> (-50, 120)
  line L2 (-50, 120) -> (-50, 0)
  line L3 (-50, 0) -> (0, 0)
  line L4 (-35, 85) -> (-15, 85)
  line L5 (-15, 85) -> (-15, 35)
  line L6 (-15, 35) -> (-35, 35)
  line L7 (-35, 35) -> (-35, 85)
  dimension "d6" = 20
  dimension "d7" = 50
  dimension "d8" = 35
  dimension "d9" = 15
  constraint horizontal L4
  constraint vertical L5
  constraint horizontal L6
  constraint vertical L7
  measures "d6" distance of L4.start L4.end
  measures "d7" distance of L4.start L6.end
  measures "d8" distance of L3 L6
  measures "d9" distance of L0 L5
extrude "Extrude2" cut sketch "Sketch2" against normal blind 20 contours L4 L5 L6 L7
move_body "Move1" bodies 1 to x (1, 0, 0) y (0, 0, -1) z (0, 1, 0) at (0, 0, 0)
sketch "Sketch3" plane through (0, 0, -45) normal (0, 0, 1) x (-1, 0, 0)
  line L0 (-170, -115) -> (-5, -115)
  line L1 (-5, -115) -> (-5, -5)
  line L2 (-5, -5) -> (-170, -5)
  line L3 (-170, -5) -> (-170, -115)
  line L4 (-55, -25) -> (-95, -25)
  line L5 (-95, -25) -> (-95, -35)
  line L6 (-95, -35) -> (-55, -35)
  line L7 (-55, -35) -> (-55, -25)
  line L8 (-55, -95) -> (-95, -95)
  line L9 (-95, -95) -> (-95, -85)
  line L10 (-95, -85) -> (-55, -85)
  line L11 (-55, -85) -> (-55, -95)
  line L12 (-123.6484, -45) -> (-163.6484, -45)
  line L13 (-163.6484, -45) -> (-163.6484, -35)
  line L14 (-163.6484, -35) -> (-123.6484, -35)
  line L15 (-123.6484, -35) -> (-123.6484, -45)
  dimension "d15" = 40
  dimension "d16" = 10
  dimension "d17" = 20
  dimension "d18" = 50
  dimension "d19" = 40
  dimension "d20" = 10
  dimension "d21" = 40
  dimension "d22" = 10
  dimension "d23" = 30
  dimension "d24" = 20
  dimension "d25" = 50
  constraint horizontal L4
  constraint vertical L5
  constraint horizontal L6
  constraint vertical L7
  constraint horizontal L8
  constraint vertical L9
  constraint horizontal L10
  constraint vertical L11
  constraint horizontal L12
  constraint vertical L13
  constraint horizontal L14
  constraint vertical L15
  measures "d15" distance of L4.start L4.end
  measures "d16" distance of L4.start L6.end
  measures "d17" distance of L2 L4
  measures "d18" horizontal distance of L1.end L4.start
  measures "d19" distance of L8.start L8.end
  measures "d20" distance of L8.start L10.end
  measures "d21" distance of L12.start L12.end
  measures "d22" distance of L12.start L14.end
  measures "d23" distance of L2 L14
  measures "d24" distance of L0 L8
  measures "d25" horizontal distance of L0.end L8.start
extrude "Extrude3" add sketch "Sketch3" along normal blind 40 contours L4 L5 L6 L7 | L8 L9 L10 L11 | L12 L13 L14 L15
sketch "Sketch4" plane through (0, 35, 0) normal (0, 1, 0) x (-1, 0, 0)
  line L0 (-95, -45) -> (-55, -45)
  line L1 (-55, -45) -> (-55, -5)
  line L2 (-55, -5) -> (-95, -5)
  line L3 (-95, -5) -> (-95, -45)
  line L4 (-63.5, -30) -> (-86.5, -30)
  line L5 (-86.5, -30) -> (-86.5, -17)
  line L6 (-86.5, -17) -> (-63.5, -17)
  line L7 (-63.5, -17) -> (-63.5, -30)
  dimension "d30" = 23
  dimension "d31" = 13
  dimension "d45" = 8.5
  constraint horizontal L4
  constraint vertical L5
  constraint horizontal L6
  constraint vertical L7
  measures "d30" distance of L4.start L4.end
  measures "d31" distance of L4.start L6.end
  measures "d45" distance of L1 L7
extrude "Extrude5" cut sketch "Sketch4" against normal blind 10 contours L4 L5 L6 L7
sketch "Sketch5" plane through (0, 45, 0) normal (0, 1, 0) x (-1, 0, 0)
  line L0 (-163.6484, -45) -> (-123.6484, -45)
  line L1 (-123.6484, -45) -> (-123.6484, -5)
  line L2 (-123.6484, -5) -> (-163.6484, -5)
  line L3 (-163.6484, -5) -> (-163.6484, -45)
  line L4 (-132.1484, -30) -> (-155.1484, -30)
  line L5 (-155.1484, -30) -> (-155.1484, -18)
  line L6 (-155.1484, -18) -> (-132.1484, -18)
  line L7 (-132.1484, -18) -> (-132.1484, -30)
  dimension "d35" = 23
  dimension "d36" = 12
  dimension "d37" = 8.5
  constraint horizontal L4
  constraint vertical L5
  constraint horizontal L6
  constraint vertical L7
  measures "d35" distance of L4.start L4.end
  measures "d36" distance of L4.start L6.end
  measures "d37" distance of L1 L7
extrude "Extrude6" cut sketch "Sketch5" against normal blind 15 contours L4 L5 L6 L7
sketch "Sketch6" plane through (0, 85, 0) normal (0, -1, 0) x (1, 0, 0)
  line L0 (55, -45) -> (95, -45)
  line L1 (95, -45) -> (95, -5)
  line L2 (95, -5) -> (55, -5)
  line L3 (55, -5) -> (55, -45)
  line L4 (63.5, -15.1434) -> (86.5, -15.1434)
  line L5 (86.5, -15.1434) -> (86.5, -28.1434)
  line L6 (86.5, -28.1434) -> (63.5, -28.1434)
  line L7 (63.5, -28.1434) -> (63.5, -15.1434)
  dimension "d40" = 23
  dimension "d41" = 13
  dimension "d42" = 8.5
  constraint horizontal L4
  constraint vertical L5
  constraint horizontal L6
  constraint vertical L7
  measures "d40" distance of L4.start L4.end
  measures "d41" distance of L4.start L6.end
  measures "d42" distance of L3 L6.end
extrude "Extrude7" cut sketch "Sketch6" against normal blind 15 contours L4 L5 L6 L7
equation "d37 = ( 17 / 2 ) * 1 mm"
equation "d42 = ( 17 / 2 ) * 1 mm"
equation "d45 = ( 17 / 2 ) * 1 mm"

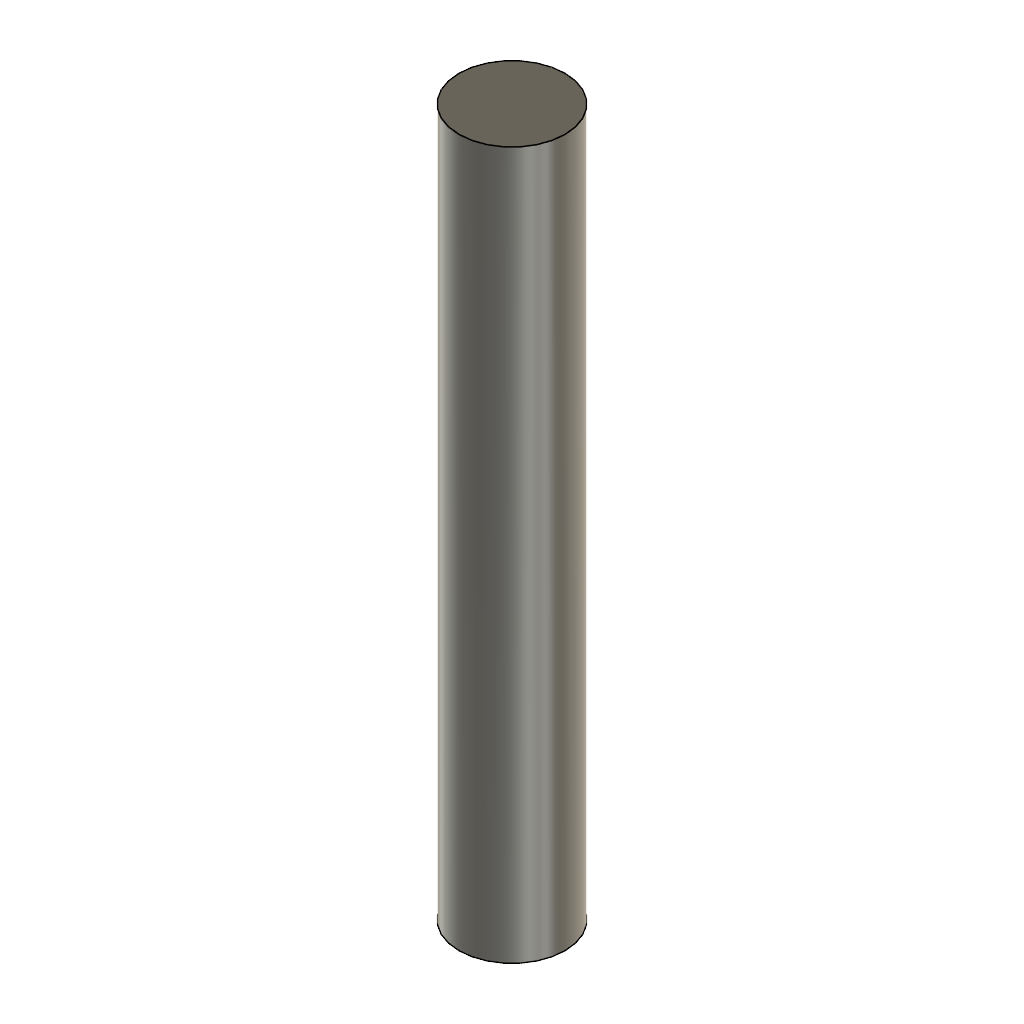
design "Connection"
part number: 2026-11-07-20-24-47-421
Autodesk Fusion 360 part; units mm, degrees
sketch "Sketch1" plane through (0, 0, 0) normal (0, 0, 1) x (1, 0, 0)
  circle A0 centre (0, 0) radius 1.5
  dimension "d1" = 3
  constraint coincident A0.centre origin
  measures "d1" diameter of A0
extrude "Extrude1" add sketch "Sketch1" along normal blind 20

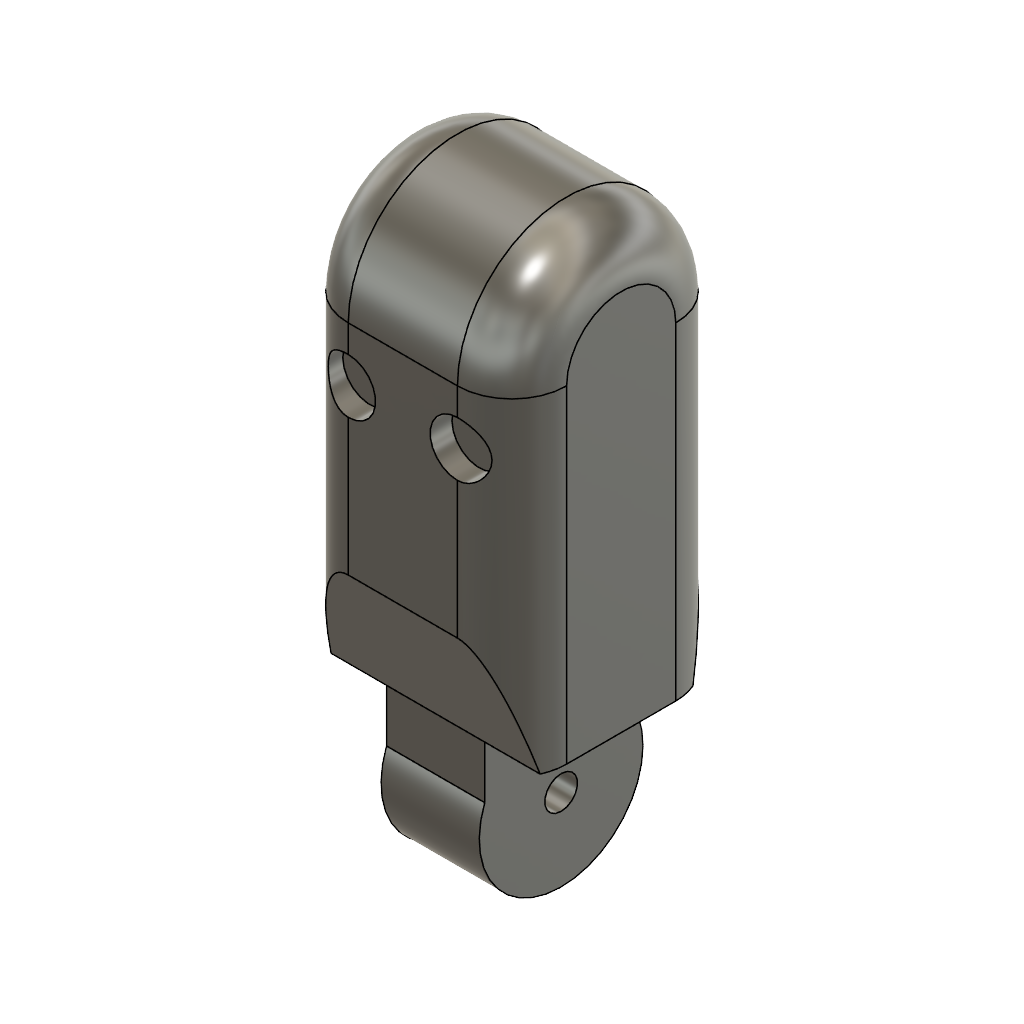
design "Index Finger DISTAL"
part number: 2026-11-03-21-33-55-123
Autodesk Fusion 360 part; units mm, degrees
sketch "Sketch1" plane through (0, 0, 0) normal (1, 0, 0) x (0, 1, 0)
  line L0 (15, 0) -> (45, 0)
  line L1 (45, 0) -> (45, -20)
  line L2 (45, -20) -> (15, -20)
  line L3 (15, -20) -> (15, 0)
  circle A0 centre (45, -10) radius 10
  dimension "d1" = 30
  dimension "d2" = 20
  dimension "d3" = 15
  dimension "d4" = 20
  constraint horizontal L0
  constraint vertical L1
  constraint horizontal L2
  constraint vertical L3
  constraint midpoint L1 A0.centre
  measures "d1" distance of L0.start L0.end
  measures "d2" distance of L0.start L2.end
  measures "d3" distance of origin L0.start
  measures "d4" diameter of A0
extrude "Extrude1" add sketch "Sketch1" along normal mid plane 20
sketch "Sketch2" plane through (0, 0, 0) normal (1, 0, 0) x (0, 1, 0)
  circle A0 centre (7.5, -10) radius 7.5
  line L0 (15, -3) -> (10.0157, -3)
  line L1 (10.0157, -3) -> (10.0157, -17.0655)
  line L2 (10.0157, -17.0655) -> (15, -17.0655)
  line L3 (15, -17.0655) -> (15, -3)
  point P0 (15, 0)
  point P1 (15, -20)
  dimension "d7" = 15
  dimension "d8" = 7.5
  dimension "d28" = 10
  constraint horizontal L0
  constraint vertical L1
  constraint horizontal L2
  constraint vertical L3
  constraint coincident A0 L1.end
  measures "d7" diameter of A0
  measures "d8" horizontal distance of origin A0.centre
  measures "d28" vertical distance of A0.centre P1
extrude "Extrude2" add sketch "Sketch2" along normal mid plane 9
hole "Hole1" at (-4.5, 7.5, -10) direction (1, 0, 0) diameter 3 end through all
sketch "Sketch4" plane through (0, 0, 0) normal (0, 0, 1) x (1, 0, 0)
  line L0 (-10, 15) -> (10, 15)
  line L1 (10, 15) -> (10, 45)
  line L2 (10, 45) -> (-10, 45)
  line L3 (-10, 45) -> (-10, 15)
  circle A0 centre (-5, 40) radius 2.5
  circle A1 centre (5, 40) radius 2.5
  dimension "d29" = 5
  dimension "d30" = 5
  measures "d29" diameter of A0
  measures "d30" diameter of A1
extrude "Extrude4" cut sketch "Sketch4" against normal blind 2 contours A0 | A1
sketch "Sketch5" plane through (10, 0, 0) normal (1, 0, 0) x (0, 0, -1)
  line L0 (20, 15) -> (20, 45)
  arc A0 (20, 45) -> (0, 45) centre (10, 45) ccw
  line L1 (0, 45) -> (0, 15)
  line L2 (0, 15) -> (20, 15)
  line L3 (17, 15) -> (20, 25)
  line L4 (17, 15) -> (20, 15)
  line L5 (20, 25) -> (20, 15)
  line L6 (0, 25) -> (3, 15)
  line L7 (3, 15) -> (0, 15)
  line L8 (0, 25) -> (0, 15)
  dimension "d33" = 10
  dimension "d34" = 3
  dimension "d37" = 3
  dimension "d38" = 10
  constraint coincident L2 L3.start
  constraint coincident L0 L3.end
  constraint coincident L0.start L2.end
  constraint coincident L1 L6.start
  constraint coincident L2 L6.end
  constraint coincident L1.end L2.start
  measures "d33" distance of L3.end L0.start
  measures "d34" distance of L3.start L0.start
  measures "d37" distance of L1.end L6.end
  measures "d38" distance of L6.start L1.end
extrude "Extrude5" cut sketch "Sketch5" against normal blind 33 contours L0 L2 L3 L4 L5 | L1 L2 L6 L7 L8
fillet "Fillet2" radius 5 3 edges at (10, 35, -20) (10, 55, -10) (10, 35, 0)
fillet "Fillet3" radius 5 3 edges at (-10, 35, 0) (-10, 55, -10) (-10, 35, -20)
